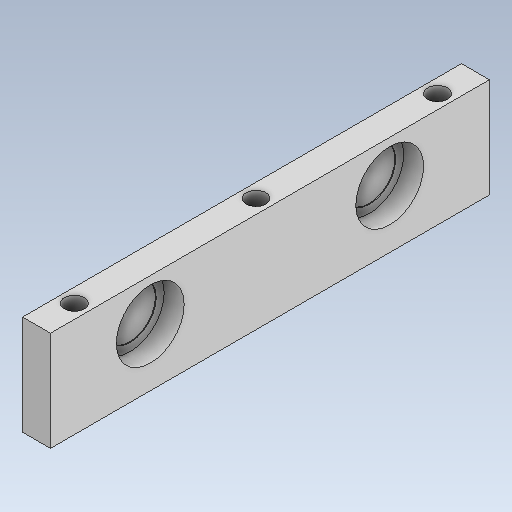
# Autodesk Inventor part: Außenseite_links
Saved by Autodesk Inventor 2026.4 (Build 304435030, 435C)
## iProperties
Created: 2026-11-20
Part Number: Außenseite_links
Material: Generisch
Document SubType Name: Modeling
Designer: weira
Density: 1 g/cm^3
Appearance: Vorgabe
Author: weira
Autodesk Inventor part; units mm, degrees
ref_plane "YZ Plane" through (0, 0, 0) normal (1, 0, 0) x (0, 1, 0)
ref_plane "XZ Plane" through (0, 0, 0) normal (0, 1, 0) x (-1, 0, 0)
ref_plane "XY Plane" through (0, 0, 0) normal (0, 0, 1) x (1, 0, 0)
sketch "Skizze1" plane through (0, 0, 0) normal (1, 0, 0) x (0, 1, 0)
  line L0 (-55, 12.5) -> (55, 12.5)
  line L1 (55, 12.5) -> (55, -12.5)
  line L2 (55, -12.5) -> (-55, -12.5)
  line L3 (-55, -12.5) -> (-55, 12.5)
  line L4 (-55, 12.5) -> (55, -12.5) construction
  line L5 (55, 12.5) -> (-55, -12.5) construction
  point P0 (0, 0)
  dimension "d0" = 25
  dimension "d1" = 110
  constraints: 12 end point, 2 midpoint, 2 parallel, 1 horizontal, 1 perpendicular
  measures "d0" distance between parallel lines of L2 L0
  measures "d1" distance of L0.start L0.end
extrude "Extrusion1" add sketch "Skizze1" along normal blind 7
sketch "Skizze2" plane through (7, 0, 0) normal (1, 0, 0) x (0, 0, -1)
  line L0 (12.5, -55) -> (12.5, 55) projected
  line L1 (12.5, 55) -> (-12.5, 55) projected
  line L2 (-12.5, 55) -> (-12.5, -55) projected
  line L3 (-12.5, -55) -> (12.5, -55) projected
  circle A0 centre (-2, -30) radius 8.5
  circle A1 centre (-2, 30) radius 8.5
  circle A2 centre (-2, -30) radius 19 construction
  circle A3 centre (-2, 30) radius 19 construction
  line L4 (-12.5, 55) -> (12.5, 55)
  line L5 (12.5, 55) -> (12.5, 51)
  line L6 (12.5, 51) -> (-12.5, 51)
  line L7 (-12.5, 51) -> (-12.5, 55)
  line L8 (12.5, -55) -> (12.5, 55) projected
  line L9 (-12.5, -55) -> (12.5, -55)
  line L10 (12.5, -55) -> (12.5, -51)
  line L11 (12.5, -51) -> (-12.5, -51)
  line L12 (-12.5, -51) -> (-12.5, -55)
  circle A4 centre (-2, -30) radius 20
  circle A5 centre (-2, 30) radius 20
  circle A6 centre (-2, -30) radius 6.5
  circle A7 centre (-2, 30) radius 6.5
  point P0 (0, 0)
  point P1 (-2, 49)
  point P2 (-12.5, 47.022)
  point P3 (12.5, 43.775)
  point P4 (-12.5, -47.022)
  point P5 (12.5, -43.775)
  point P6 (-12.5, -51)
  dimension "d10" = 38
  dimension "d4" = 14.5
  dimension "d5" = 14.5
  dimension "d6" = 25
  dimension "d7" = 17
  dimension "d8" = 17
  dimension "d9" = 38
  dimension "d11" = 60
  dimension "d12" = 25
  dimension "d13" = 110
  dimension "d14" = 4
  dimension "d15" = 4
  dimension "d16" = 40
  dimension "d19" = 13
  dimension "d20" = 13
  constraints: 16 end point, 8 coincident, 7 centre point, 4 parallel, 2 horizontal, 2 perpendicular, 2 point on line, 1 vertical alignment, 2 other
  measures "d4" distance from line of L0 point (-2, -30)
  measures "d5" distance from line of L0 point (-2, 30)
  measures "d6" distance between parallel lines of L0 L2
  measures "d7" diameter of A0
  measures "d8" diameter of A1
  measures "d9" diameter of A2
  measures "d11" distance of A1.centre A0.centre
  measures "d12" distance from line of L3 A0.centre
  measures "d13" distance of L0.start L0.end
  measures "d14" distance between parallel lines of L1 L6
  measures "d15" distance between parallel lines of L3 L11
  measures "d16" diameter of A4
  measures "d19" diameter of A7
  measures "d20" diameter of A6
extrude "Extrusion2" cut sketch "Skizze2" against normal blind 5 contours A0 | A1 | A6 | A7
extrude "Extrusion3" cut sketch "Skizze2" against normal blind 5.2 contours A6 | A7
sketch "Skizze4" plane through (0, -55, 12.5) normal (0, 0, 1) x (1, 0, 0)
  line L0 (0, 110) -> (0, 0) projected
  line L1 (0, 0) -> (7, 0) projected
  line L2 (7, 110) -> (7, 0) projected
  line L3 (0, 110) -> (7, 110) projected
  line L4 (3.5, 0) -> (3.5, 110) construction
  line L5 (2, 93.5) -> (2, 76.5) projected
  line L6 (2, 33.5) -> (2, 16.5) projected
  circle A0 centre (3.5, 100.5) radius 2.5 construction
  circle A1 centre (3.5, 9.5) radius 2.5 construction
  line L7 (0, 110) -> (7, 110) projected
  line L8 (0, 16.5) -> (7, 16.5) construction
  line L9 (0, 93.5) -> (7, 93.5) construction
  line L10 (0, 33.5) -> (7, 33.5) construction
  line L11 (0, 0) -> (0, 110) projected
  line L12 (0, 76.5) -> (7, 76.5) construction
  line L13 (0, 55) -> (7, 55) construction
  point P0 (3.5, 55)
  dimension "d23" = 7
  dimension "d24" = 3.5
  dimension "d25" = 110
  dimension "d26" = 55
  dimension "d27" = 5
  dimension "d28" = 5
  dimension "d31" = 9.5
  dimension "d32" = 9.5
  constraints: 12 end point, 10 point on line, 5 midpoint, 4 perpendicular, 2 centre point, 2 coincident
  measures "d23" distance between parallel lines of L2 L0
  measures "d24" distance between parallel lines of L0 L4
  measures "d25" distance of L2.start L1.end
  measures "d26" distance from line of L3 point (3.5, 55)
  measures "d27" diameter of A0
  measures "d28" diameter of A1
  measures "d31" distance from line of L1 A1.centre
  measures "d32" distance of point (3.5, 110) A0.centre
hole "Bohrung1" at (3.5, -45.5, 12.5) at (3.5, 45.5, 12.5) at (3.5, 0, 12.5) direction (0, 0, -1) diameter 5 end through all
equation "\"d5\" = d4"
equation "\"d7\" = d8"
equation "\"d9\" = d10"
equation "\"d12\" = -0.5 * d11 + 0.5 * d13"
equation "\"d15\" = d14"
equation "\"d20\" = d19"
equation "\"d28\" = d27"
equation "\"d32\" = d31"
